Autodesk Fusion 360 part; units mm, degrees
(part 2 of 3)
sketch "Sketch2" plane through (0, 0, 6.35) normal (0, 0, 1) x (-1, 0, 0)
  line L0 (0, -44.45) -> (0, 0)
  line L1 (0, 0) -> (-41.148, 0)
  line L2 (-41.148, 0) -> (-41.148, -44.45)
  line L3 (-41.148, -44.45) -> (0, -44.45)
  line L4 (0, 0) -> (0, -38.608) construction
  line L5 (0, -38.608) -> (-41.148, -38.608)
  line L6 (-41.148, -38.608) -> (-41.148, -44.45)
  line L7 (-41.148, -44.45) -> (0, -44.45)
  line L8 (0, -44.45) -> (0, -38.608)
  dimension "d5" = 38.608
  constraint coincident L0.end L1.start
  constraint perpendicular L1 L4
  constraint horizontal L5
  constraint vertical L6
  constraint horizontal L7
  constraint vertical L8
  constraint coincident L2.end L3.start
  measures "d5" distance of L0.end L4.end
extrude "Extrude2" add sketch "Sketch2" along normal blind 22.86 contours L0 L2 L3 L5 L6 L7 L8
sketch "Sketch3" plane through (0, 0, 29.21) normal (0, 0, 1) x (-1, 0, 0)
  line L0 (0, -44.45) -> (0, -38.608)
  line L1 (0, -38.608) -> (-41.148, -38.608)
  line L2 (-41.148, -38.608) -> (-41.148, -44.45)
  line L3 (-41.148, -44.45) -> (0, -44.45)
  line L4 (-41.148, -44.45) -> (0, -44.45)
  line L5 (0, -44.45) -> (0, 0)
  line L6 (0, 0) -> (-41.148, 0)
  line L7 (-41.148, 0) -> (-41.148, -44.45)
  constraint horizontal L4
  constraint vertical L5
  constraint horizontal L6
  constraint vertical L7
  constraint coincident L5.end L6.start
  constraint coincident L2.end L3.start
extrude "Extrude3" add sketch "Sketch3" along normal blind 6.35
sketch "Sketch4" plane through (0, 44.45, 0) normal (0, 1, 0) x (-1, 0, 0)
  line L0 (-41.148, 0) -> (0, 0)
  line L1 (0, 0) -> (0, 35.56)
  line L2 (0, 35.56) -> (-41.148, 35.56)
  line L3 (-41.148, 35.56) -> (-41.148, 0)
  line L4 (-41.148, 17.78) -> (-33.528, 17.78) construction
  line L5 (-33.528, 17.78) -> (-30.353, 17.78) construction
  line L6 (-30.353, 8.255) -> (-41.148, 8.255)
  line L7 (-41.148, 8.255) -> (-41.148, 27.305)
  line L8 (-41.148, 27.305) -> (-30.353, 27.305)
  line L9 (-30.353, 27.305) -> (-30.353, 8.255)
  line L10 (-20.574, 35.56) -> (-20.574, 0) construction
  line L11 (-10.795, 27.305) -> (-10.795, 8.255)
  line L12 (0, 27.305) -> (-10.795, 27.305)
  line L13 (0, 8.255) -> (0, 27.305)
  line L14 (-10.795, 8.255) -> (0, 8.255)
  dimension "d10" = 7.62
  dimension "d11" = 3.175
  dimension "d13" = 19.05
  constraint midpoint L3 L4.start
  constraint perpendicular L3 L4
  constraint horizontal L5
  constraint horizontal L6
  constraint vertical L7
  constraint horizontal L8
  constraint vertical L9
  constraint midpoint L5.end L9
  constraint midpoint L2 L10.start
  constraint midpoint L0 L10.end
  constraint symmetric L6.start L10 L11.end
  constraint symmetric L6.end L10 L13.start
  constraint symmetric L7.end L10 L12.start
  constraint symmetric L8.end L10 L11.start
  measures "d10" distance of L4.start L4.end
  measures "d11" distance of L4.end L5.end
  measures "d13" distance of L6.start L8.end
extrude "Extrude4" cut sketch "Sketch4" against normal up to surface (5.842 mm away) contours L3 L6 L7 L8 L9 | L1 L11 L12 L13 L14
fillet "Fillet2" radius 2.54 6 edges at (20.574, 0, 29.21) (41.148, 0, 32.385) (0, 0, 32.385) (20.574, 0, 6.35) (41.148, 0, 3.175) (0, 0, 3.175)
fillet "Fillet4" radius 2.54 4 edges at (30.353, 41.529, 8.255) (10.795, 41.529, 8.255) (10.795, 41.529, 27.305) (30.353, 41.529, 27.305)
fillet "Fillet4" radius 2.54 2 edges at (20.574, 38.608, 6.35) (20.574, 38.608, 29.21)
fillet "Fillet5" radius 1.778 4 edges at (41.148, 41.4887, 8.255) (41.148, 41.4887, 27.305) (0, 41.4887, 8.255) (0, 41.4887, 27.305)
sketch "Sketch5" plane through (30.353, 0, 0) normal (1, 0, 0) x (0, 1, 0)
  line L0 (44.45, 24.765) -> (38.608, 24.765)
  line L1 (38.608, 24.765) -> (38.608, 10.795)
  line L2 (38.608, 10.795) -> (44.45, 10.795)
  line L3 (44.45, 10.795) -> (44.45, 24.765)
  line L4 (38.608, 17.78) -> (44.45, 17.78) construction
  circle A0 centre (41.151, 17.78) radius 1.4
  line L5 (38.608, 17.78) -> (39.751, 17.78) construction
  dimension "d28" = 2.8
  dimension "d29" = 1.143
  constraint midpoint L1 L4.start
  constraint midpoint L3 L4.end
  constraint coincident L4 A0.centre
  constraint coincident A0 L5.end
  constraint coincident L4 L5.end
  measures "d28" diameter of A0
  measures "d29" distance of L4.start L5.end
extrude "Extrude5" cut sketch "Sketch5" against normal up to surface (19.558 mm away) contours A0

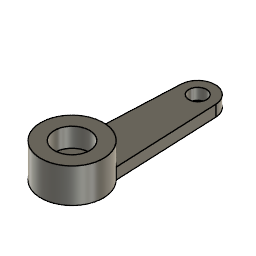
design "MicroServo horn"
Autodesk Fusion 360 part; units mm, degrees
sketch "Sketch1" plane through (0, 0, 0) normal (0, 0, 1) x (1, 0, 0)
  circle A0 centre (0, 0) radius 3.5243
  line L0 (-2.4892, 2.4948) -> (-1.9685, 14.2773)
  line L1 (2.4892, 2.4948) -> (1.9685, 14.2773)
  arc A1 (1.9685, 14.2773) -> (-1.9685, 14.2773) centre (0, 14.1903) ccw
  line L2 (-12.7, 16.1608) -> (12.7, 16.1608)
  line L3 (-12.7, -3.5242) -> (12.7, -3.5243)
  circle A2 centre (0, 14.1903) radius 1
  dimension "d1" = 7.0485
  dimension "d2" = 4.9784
  dimension "d5" = 19.685
  dimension "d7" = 3.937
  dimension "d8" = 2
  dimension "d9" = 25.4
  dimension "d10" = 12.7
  constraint coincident A0.centre origin
  constraint coincident A0 L0.start
  constraint coincident A0 L1.start
  constraint tangent L0 A1
  constraint horizontal L2
  constraint tangent A1 L2
  constraint vertical A0.centre A1.centre
  constraint horizontal L0.end L1.end
  constraint tangent A0 L3
  constraint horizontal L3
  constraint horizontal L0.start L1.start
  constraint concentric A1 A2
  constraint vertical L2.start L3.start
  constraint vertical L2.end L3.end
  measures "d1" diameter of A0
  measures "d2" horizontal distance of L0.start L1.start
  measures "d5" distance of L2 L3
  measures "d7" distance of L0.end L1.end
  measures "d8" diameter of A2
  measures "d9" distance of L2.start L2.end
  measures "d10" horizontal distance of A1.centre L2.start
extrude "Extrude1" add sketch "Sketch1" along normal blind 1.27
extrude "Extrude2" add sketch "Sketch1" along normal blind 3.8735 contours A0
sketch "Sketch2" plane through (0, 0, 3.8735) normal (0, 0, 1) x (-1, 0, 0)
  circle A0 centre (0, 0) radius 3.5242
  circle A1 centre (0, 0) radius 1.9812
  dimension "d15" = 3.9624
  constraint coincident A0.centre A1.centre
  measures "d15" diameter of A1
extrude "Extrude3" cut sketch "Sketch2" against normal blind 2.159 contours A1

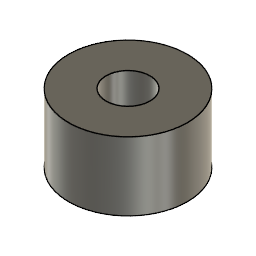
design "Shaft Collar"
Autodesk Fusion 360 part; units mm, degrees
sketch "Sketch1" plane through (0, 0, 0) normal (0, 0, 1) x (1, 0, 0)
  circle A0 centre (0, 0) radius 5.4991
  circle A1 centre (0, 0) radius 2.032
  dimension "d1" = 10.9982
  dimension "d2" = 4.064
  constraint coincident A0.centre A1.centre
  constraint concentric A0 A1
  measures "d1" diameter of A0
  measures "d2" diameter of A1
extrude "Extrude1" add sketch "Sketch1" along normal blind 6.35

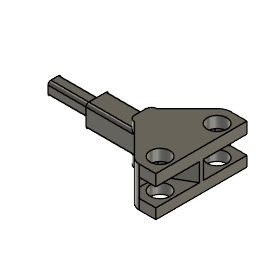
design "Wheel mount"
Autodesk Fusion 360 part; units mm, degrees
sketch "Sketch1" plane through (0, 0, 0) normal (0, 0, 1) x (1, 0, 0)
  line L0 (1.27, -2.54) -> (8.89, -2.54)
  line L1 (8.89, -2.54) -> (8.89, 2.54)
  line L2 (8.89, 2.54) -> (1.27, 2.54)
  line L3 (0, 1.27) -> (0, -1.27)
  line L4 (16.51, 10.16) -> (16.51, -10.16)
  line L5 (8.89, -10.16) -> (8.89, 10.16)
  arc A0 (1.27, 2.54) -> (0, 1.27) centre (1.27, 1.27) ccw
  arc A1 (0, -1.27) -> (1.27, -2.54) centre (1.27, -1.27) ccw
  circle A2 centre (10.795, 6.35) radius 2.2
  circle A3 centre (10.795, -6.35) radius 2.2
  line L6 (9.9421, 10.16) -> (16.51, 10.16)
  line L7 (9.9421, -10.16) -> (16.51, -10.16)
  line L8 (1.27, -2.54) -> (8.1461, -9.4161)
  line L9 (1.27, 2.54) -> (8.1461, 9.4161)
  arc A4 (9.9421, 10.16) -> (8.1461, 9.4161) centre (9.9421, 7.62) ccw
  arc A5 (8.1461, -9.4161) -> (9.9421, -10.16) centre (9.9421, -7.62) ccw
  line L10 (13.6525, 10.16) -> (13.6525, -10.16)
  dimension "d1" = 1.27
  dimension "d2" = 1.27
  dimension "d5" = 4.4
  dimension "d6" = 4.4
  dimension "d8" = 20.32
  dimension "d9" = 7.62
  dimension "d10" = 1.905
  dimension "d13" = 2.54
  dimension "d14" = 20.32
  dimension "d15" = 2.54
  dimension "d16" = 2.54
  dimension "d17" = 45
  dimension "d18" = 12.7
  dimension "d19" = 6.35
  dimension "d31" = 2.8575
  constraint horizontal L0
  constraint vertical L1
  constraint horizontal L2
  constraint vertical L3
  constraint vertical L4
  constraint vertical L5
  constraint midpoint L1 L5
  constraint tangent L2 A0
  constraint tangent L3 A0
  constraint tangent L0 A1
  constraint tangent L3 A1
  constraint midpoint origin L3
  constraint perpendicular L4 L6
  constraint coincident L5.end L9
  constraint coincident L5.end L6
  constraint tangent L9 A4
  constraint tangent L6 A4
  constraint coincident L5.start L8
  constraint coincident L5.start L7
  constraint tangent L8 A5
  constraint tangent L7 A5
  constraint vertical A2.centre A3.centre
  constraint coincident L6 L10.start
  constraint coincident L7 L10.end
  constraint perpendicular L7 L10
  measures "d1" radius of A0
  measures "d2" radius of A1
  measures "d5" diameter of A2
  measures "d6" diameter of A3
  measures "d8" distance of L4.start L4.end
  measures "d9" distance of L4 L5
  measures "d10" distance of L5 A3.centre
  measures "d13" distance of L3.start L3.end
  measures "d14" distance of L5.end L5.start
  measures "d15" radius of A4
  measures "d16" radius of A5
  measures "d17" angle of L0 L8
  measures "d18" vertical distance of A2.centre A3.centre
  measures "d19" vertical distance of origin A2.centre
  measures "d31" distance of A3.centre L10
extrude "Extrude1" add sketch "Sketch1" along normal blind 6.35 contours L0 L1 L2 L3 L5 A0 A1 | L0 L5 A3 L8 A5 | L1 L5 A2 A3 L6 L7 A4 A5 L10 | L2 L5 A2 L9 A4
sketch "Sketch3" plane through (13.6525, 0, 0) normal (1, 0, 0) x (0, 1, 0)
  line L0 (-10.16, 0) -> (10.16, 0)
  line L1 (10.16, 0) -> (10.16, 6.35)
  line L2 (10.16, 6.35) -> (-10.16, 6.35)
  line L3 (-10.16, 6.35) -> (-10.16, 0)
  line L4 (3.81, 5.08) -> (8.89, 5.08)
  line L5 (8.89, 5.08) -> (8.89, 1.27)
  line L6 (8.89, 1.27) -> (3.81, 1.27)
  line L7 (3.81, 1.27) -> (3.81, 5.08)
  line L8 (-10.16, 0) -> (10.16, 0)
  line L9 (10.16, 0) -> (10.16, 6.35)
  line L10 (10.16, 6.35) -> (-10.16, 6.35)
  line L11 (-10.16, 6.35) -> (-10.16, 0)
  line L12 (-8.89, 5.08) -> (-3.81, 5.08)
  line L13 (-3.81, 5.08) -> (-3.81, 1.27)
  line L14 (-3.81, 1.27) -> (-8.89, 1.27)
  line L15 (-8.89, 1.27) -> (-8.89, 5.08)
  dimension "d25" = 3.81
  dimension "d26" = 5.08
  dimension "d27" = 1.27
  dimension "d28" = 1.27
  dimension "d32" = 5.08
  dimension "d33" = 1.27
  dimension "d34" = 1.27
  dimension "d35" = 3.81
  constraint horizontal L4
  constraint vertical L5
  constraint horizontal L6
  constraint vertical L7
  constraint horizontal L12
  constraint vertical L13
  constraint horizontal L14
  constraint vertical L15
  measures "d25" distance of L4.end L5.end
  measures "d26" distance of L4.start L4.end
  measures "d27" distance of L1 L5
  measures "d28" distance of L0 L6
  measures "d32" distance of L12.start L12.end
  measures "d33" distance of L3 L15
  measures "d34" distance of L0 L14
  measures "d35" distance of L12.end L13.end
extrude "Extrude3" cut sketch "Sketch3" against normal blind 5.842 contours L4 L5 L6 L7 | L12 L13 L14 L15
sketch "Sketch2" plane through (0, 0, 0) normal (-1, 0, 0) x (0, -1, 0)
  line L0 (-1.27, 0) -> (1.27, 0)
  line L1 (1.27, 0) -> (1.27, 6.35)
  line L2 (1.27, 6.35) -> (-1.27, 6.35)
  line L3 (-1.27, 6.35) -> (-1.27, 0)
  line L4 (2.54, 5.715) -> (-2.54, 5.715)
  line L5 (-2.54, 5.715) -> (-2.54, 0.635)
  line L6 (-2.54, 0.635) -> (2.54, 0.635)
  line L7 (2.54, 0.635) -> (2.54, 5.715)
  line L8 (2.54, 5.715) -> (-2.54, 0.635) construction
  line L9 (-2.54, 5.715) -> (2.54, 0.635) construction
  point P0 (0, 3.175)
  dimension "d20" = 5.08
  dimension "d21" = 5.08
  dimension "d22" = 3.175
  constraint horizontal L4
  constraint perpendicular L4 L5
  constraint parallel L4 L6
  constraint parallel L5 L7
  constraint coincident L8 P0
  constraint coincident L9 P0
  constraint vertical origin P0
  measures "d20" distance of L4.end L5.end
  measures "d21" distance of L5.end L6.end
  measures "d22" vertical distance of origin P0
extrude "Extrude2" add sketch "Sketch2" along normal blind 19.05 contours L3 L4 L5 L6 | L1 L3 L4 L6 | L1 L4 L6 L7
draft "Draft1" angle 30 neutral plane through (7.8105, 0, 0) pull (1, 0, 0) 1 faces at (11.7052, -8.89, 2.54)
draft "Draft2" angle 30 neutral plane through (7.8105, 0, 0) pull (1, 0, 0) 1 faces at (11.7052, -3.81, 3.81)
draft "Draft3" angle 30 neutral plane through (7.8105, 0, 0) pull (1, 0, 0) 1 faces at (11.7052, 3.81, 2.54)
draft "Draft4" angle 30 neutral plane through (7.8105, 0, 0) pull (1, 0, 0) 1 faces at (9.7578, 8.89, 3.81)
extrude "Extrude4" add 1 faces at (3.4502, 0.4745, 6.35) along direction (0, 0, 1) blind 1.27
extrude "Extrude5" add 1 faces at (3.4502, 0.4745, 0) along direction (0, 0, -1) blind 1.27
extrude "Extrude6" cut 2 faces at (10.5895, -2.8174, 1.27) (10.5895, 2.8174, 1.27) along direction (0, 0, -1) blind 0.254
sketch "Sketch5" plane through (-19.05, 0, 0) normal (-1, 0, 0) x (0, -1, 0)
  line L0 (2.54, 0.635) -> (2.54, 5.715)
  line L1 (2.54, 5.715) -> (-2.54, 5.715)
  line L2 (-2.54, 5.715) -> (-2.54, 0.635)
  line L3 (-2.54, 0.635) -> (2.54, 0.635)
  line L4 (1.4875, 4.6625) -> (-1.4875, 4.6625)
  line L5 (-1.4875, 4.6625) -> (-1.4875, 1.6875)
  line L6 (-1.4875, 1.6875) -> (1.4875, 1.6875)
  line L7 (1.4875, 1.6875) -> (1.4875, 4.6625)
  line L8 (1.4875, 4.6625) -> (-1.4875, 1.6875) construction
  line L9 (-1.4875, 4.6625) -> (1.4875, 1.6875) construction
  point P0 (0, 3.175)
  point P1 (-10.16, -1.27)
  dimension "d50" = 2.975
  dimension "d51" = 2.975
  dimension "d52" = 4.445
  constraint horizontal L4
  constraint perpendicular L4 L5
  constraint parallel L4 L6
  constraint parallel L5 L7
  constraint coincident L8 P0
  constraint coincident L9 P0
  constraint vertical origin P0
  measures "d50" distance of L5 L7
  measures "d51" distance of L4 L6
  measures "d52" vertical distance of P0 P1
extrude "Extrude7" cut sketch "Sketch5" against normal blind 9.525
extrude "Extrude8" add 2 faces at (0, 1.6933, 2.54) (0, -1.6598, 3.81) along direction (1, 0, 0) blind 2.286
fillet "Fillet1" radius 0.635 8 edges at (-4.1275, 2.54, 5.715) (-4.1275, 2.54, 0.635) (-14.2875, 1.4875, 4.6625) (-14.2875, 1.4875, 1.6875) (-14.2875, -1.4875, 4.6625) (-14.2875, -1.4875, 1.6875) (-4.1275, -2.54, 5.715) (-4.1275, -2.54, 0.635)
equation "d10 = 0.125 in - 0.05 in"
equation "d31 = 0.165 * 0.5 in + 0.03 in"
equation "d50 = 0.125 in - 0.2 mm"
equation "d51 = 0.125 in - 0.2 mm"

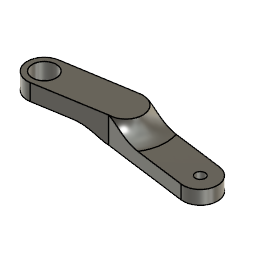
design "Right Control Arm"
Autodesk Fusion 360 part; units mm, degrees
sketch "Sketch1" plane through (0, 0, 0) normal (0, 0, 1) x (1, 0, 0)
  circle A0 centre (0, 0) radius 2.2
  circle A1 centre (28.829, 0) radius 0.9
  circle A2 centre (0, 0) radius 3.175
  circle A3 centre (28.829, 0) radius 3.175
  circle A4 centre (12.954, 2.0955) radius 3.175
  line L0 (28.407994, -3.146963) -> (12.954, -1.0795)
  line L1 (0.517136, -3.132602) -> (12.954, -1.0795)
  line L2 (29.244496, 3.147696) -> (13.369496, 5.243196)
  line L3 (-0.507012, 3.134256) -> (12.446988, 5.229756)
  dimension "d1" = 1.8
  dimension "d2" = 4.4
  dimension "d3" = 28.829
  dimension "d4" = 6.35
  dimension "d5" = 6.35
  dimension "d12" = 6.35
  dimension "d22" = 15.875
  dimension "d23" = 2.0955
  constraint coincident A0.centre A2.centre
  constraint concentric A1 A3
  constraint horizontal A0.centre A1.centre
  constraint coincident A4 L0.end
  constraint tangent A4 L2
  constraint tangent A4 L3
  constraint tangent A3 L2
  constraint tangent A3 L0
  constraint tangent A2 L1
  constraint tangent A2 L3
  constraint vertical A4.centre L0.end
  measures "d1" diameter of A1
  measures "d2" diameter of A0
  measures "d3" distance of A0.centre A1.centre
  measures "d4" diameter of A3
  measures "d5" diameter of A2
  measures "d12" diameter of A4
  measures "d22" horizontal distance of A1.centre A4.centre
  measures "d23" vertical distance of A1.centre A4.centre
extrude "Extrude1" add sketch "Sketch1" along normal blind 2.54 contours A4 | A3 A4 L0 L2 | A3 picked at (13.359471, 1.020697) picked at (22.492534, 0.825939) picked at (28.326881, -2.357846)
extrude "Extrude4" add sketch "Sketch1" along normal blind 5.588 contours A4 picked at (13.359471, 1.020697)
extrude "Extrude3" add sketch "Sketch1" along normal blind 5.588 and the other way blind -1.778 contours A2 | A2 A4 L1 L3 | A4 picked at (-0.65517, 2.767544) picked at (7.597762, 1.223874) picked at (13.359471, 1.020697)
extrude "Extrude5" cut 1 faces at (9.192139, 1.492716, 5.588) along direction (0, 0, -1) blind 0.762
fillet "Fillet1" radius 5.08 1 edges at (16.122167, 1.887304, 2.54)
fillet "Fillet2" radius 5.08 1 edges at (9.789202, 1.841177, 1.778)
sketch "Sketch2" plane through (0, 0, 0) normal (0, 0, -1) x (1, 0, 0)
  circle A0 centre (28.2448, 0) radius 1.5
  line L0 (16.8148, -3.175) -> (28.2448, -3.175)
  arc A1 (28.2448, -3.175) -> (28.2448, 3.175) centre (28.2448, 0) ccw
  line L1 (28.2448, 3.175) -> (16.8148, 3.175)
  circle A2 centre (0, 0) radius 2.0955
  circle A3 centre (0, 0) radius 3.175
  arc A4 (16.8148, 3.175) -> (16.8148, -3.175) centre (16.8148, 0) ccw
  dimension "d8" = 4.191
  dimension "d9" = 6.35
  measures "d8" diameter of A2
  measures "d9" diameter of A3
extrude "Extrude2" [suppressed]
equation "d3 = 1.235 in - 0.1 in"
equation "d23 = ( 0.165 / 2 ) * 1 in"

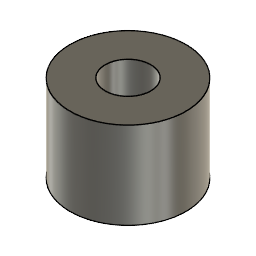
design "Front bushing"
Autodesk Fusion 360 part; units mm, degrees
sketch "Sketch1" plane through (0, 0, 0) normal (0, 0, 1) x (1, 0, 0)
  circle A0 centre (0, 0) radius 6.35
  circle A1 centre (0, 0) radius 2.4956
  dimension "d1" = 12.7
  dimension "d2" = 4.9911
  constraint coincident A0.centre A1.centre
  measures "d1" diameter of A0
  measures "d2" diameter of A1
extrude "Extrude1" add sketch "Sketch1" along normal blind 9.525

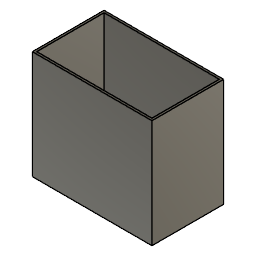
design "Recepticle"
Autodesk Fusion 360 part; units mm, degrees
sketch "Sketch1" plane through (0, 0, 0) normal (0, 0, 1) x (1, 0, 0)
  line L0 (0, 0) -> (127, 0)
  line L1 (127, 0) -> (127, 76.2)
  line L2 (127, 76.2) -> (0, 76.2)
  line L3 (0, 76.2) -> (0, 0)
  line L4 (124.6819, 73.8819) -> (2.3181, 73.8819)
  line L5 (2.3181, 73.8819) -> (2.3181, 2.3181)
  line L6 (2.3181, 2.3181) -> (124.6819, 2.3181)
  line L7 (124.6819, 2.3181) -> (124.6819, 73.8819)
  dimension "d1" = 127
  dimension "d2" = 76.2
  dimension "d3" = -2.3181
  constraint horizontal L0
  constraint vertical L1
  constraint horizontal L2
  constraint vertical L3
  constraint coincident L0.start L3.end
  measures "d1" distance of L0.start L0.end
  measures "d2" distance of L0.start L2.end
extrude "Extrude1" add sketch "Sketch1" along normal blind 115
extrude "Extrude2" add sketch "Sketch1" along normal blind 2.54 contours L4 L5 L6 L7

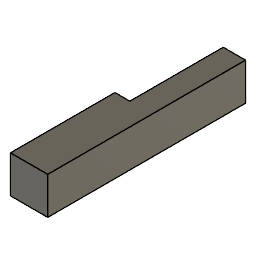
design "Right Fake Cross Beam"
Autodesk Fusion 360 part; units mm, degrees
sketch "Sketch1" plane through (0, 0, 0) normal (1, 0, 0) x (0, 1, 0)
  circle A0 centre (0, 0) radius 2.1971
  circle A1 centre (25.4, 0) radius 2.1971
  line L0 (10.16, 2.54) -> (15.24, 2.54)
  line L1 (15.24, 2.54) -> (15.24, -2.54)
  line L2 (15.24, -2.54) -> (10.16, -2.54)
  line L3 (10.16, -2.54) -> (10.16, 2.54)
  line L4 (-6.35, 4.7625) -> (31.75, 4.7625)
  line L5 (31.75, 4.7625) -> (31.75, -4.7625)
  line L6 (31.75, -4.7625) -> (-6.35, -4.7625)
  line L7 (-6.35, -4.7625) -> (-6.35, 4.7625)
  dimension "d1" = 25.4
  dimension "d2" = 4.3942
  dimension "d3" = 4.3942
  dimension "d4" = 5.08
  dimension "d5" = 5.08
  dimension "d6" = 2.54
  dimension "d7" = 10.16
  dimension "d8" = 9.525
  dimension "d9" = 38.1
  dimension "d10" = 4.7625
  dimension "d11" = 6.35
  constraint horizontal A0.centre A1.centre
  constraint horizontal L0
  constraint vertical L1
  constraint horizontal L2
  constraint vertical L3
  constraint coincident A0.centre origin
  constraint horizontal L4
  constraint vertical L5
  constraint horizontal L6
  constraint vertical L7
  measures "d1" distance of A0.centre A1.centre
  measures "d2" diameter of A0
  measures "d3" diameter of A1
  measures "d4" distance of L0.start L0.end
  measures "d5" distance of L0.start L2.end
  measures "d6" distance of A0.centre L0
  measures "d7" horizontal distance of A0.centre L2.end
  measures "d8" distance of L4.start L6.end
  measures "d9" distance of L4.start L4.end
  measures "d10" distance of A0.centre L4
  measures "d11" distance of A0.centre L7
extrude "Extrude1" add sketch "Sketch1" along normal blind 2.54 contours A0 | A1 | L0 L1 L2 L3 | L4 L5 L6 L7 makes body 1
sketch "Sketch2" plane through (2.54, 0, 0) normal (1, 0, 0) x (0, 1, 0)
  line L0 (-6.35, -4.7625) -> (31.75, -4.7625)
  line L1 (31.75, -4.7625) -> (31.75, 4.7625)
  line L2 (31.75, 4.7625) -> (-6.35, 4.7625)
  line L3 (-6.35, 4.7625) -> (-6.35, -4.7625)
  line L4 (31.75, 4.7625) -> (-6.35, 4.7625)
  line L5 (-6.35, 4.7625) -> (-6.35, -4.7625)
  line L6 (-6.35, -4.7625) -> (31.75, -4.7625)
  line L7 (31.75, -4.7625) -> (31.75, 4.7625)
  circle A0 centre (0, 0) radius 2.1971
  circle A1 centre (25.4, 0) radius 2.1971
  dimension "d14" = 4.3942
  dimension "d15" = 4.3942
  constraint horizontal L4
  constraint vertical L5
  constraint horizontal L6
  constraint vertical L7
  constraint coincident L0.start L3.end
  constraint coincident L1.end L2.start
  measures "d14" diameter of A0
  measures "d15" diameter of A1
extrude "Extrude2" add sketch "Sketch2" along normal blind 3.81 contours L0 L1 L2 L3 L4 L5 L6 L7 | A0 | A1 bodies 1
sketch "Sketch3" plane through (0, -6.35, 0) normal (0, -1, 0) x (1, 0, 0)
  line L0 (0, 4.7625) -> (0, -4.7625)
  line L1 (0, -4.7625) -> (6.35, -4.7625)
  line L2 (6.35, -4.7625) -> (6.35, 4.7625)
  line L3 (6.35, 4.7625) -> (0, 4.7625)
  line L4 (0, 4.7625) -> (6.35, 4.7625)
  line L5 (6.35, 4.7625) -> (6.35, -4.7625)
  line L6 (6.35, -4.7625) -> (0, -4.7625)
  line L7 (0, -4.7625) -> (0, 4.7625)
  constraint horizontal L4
  constraint vertical L5
  constraint horizontal L6
  constraint vertical L7
  constraint coincident L1.end L2.start
  constraint coincident L0.start L3.end
extrude "Extrude3" add sketch "Sketch3" along normal blind 127 bodies 1
sketch "Sketch4" plane through (6.35, 0, 0) normal (1, 0, 0) x (0, 1, 0)
  line L0 (31.75, -4.7625) -> (31.75, 4.7625)
  line L1 (31.75, 4.7625) -> (-133.35, 4.7625)
  line L2 (-133.35, 4.7625) -> (-133.35, -4.7625)
  line L3 (-133.35, -4.7625) -> (31.75, -4.7625)
  circle A0 centre (-22.225, -1.5875) radius 1.6
  circle A1 centre (-47.625, -1.5875) radius 1.6
  dimension "d20" = 3.2
  dimension "d21" = 3.2
  dimension "d24" = 6.35
  dimension "d25" = 22.225
  dimension "d48" = 25.4
  constraint horizontal A0.centre A1.centre
  measures "d20" diameter of A0
  measures "d21" diameter of A1
  measures "d24" distance of L1 A0.centre
  measures "d25" horizontal distance of origin A0.centre
  measures "d48" distance of A0.centre A1.centre
sketch "Sketch5" plane through (0, -133.35, 0) normal (0, -1, 0) x (1, 0, 0)
  line L0 (0, -4.7625) -> (6.35, -4.7625)
  line L1 (6.35, -4.7625) -> (6.35, 4.7625)
  line L2 (6.35, 4.7625) -> (0, 4.7625)
  line L3 (0, 4.7625) -> (0, -4.7625)
  line L4 (0, -4.7625) -> (6.35, -4.7625)
  line L5 (6.35, -4.7625) -> (6.35, 1.5875)
  line L6 (6.35, 1.5875) -> (0, 1.5875)
  line L7 (0, 1.5875) -> (0, -4.7625)
  dimension "d29" = 6.35
  constraint horizontal L4
  constraint vertical L5
  constraint horizontal L6
  constraint vertical L7
  constraint coincident L1 L5.end
  constraint coincident L0.start L3.end
  measures "d29" distance of L0.end L5.end
extrude "Extrude5" cut sketch "Sketch5" against normal blind 67.945 contours L1 L2 L3 L6 bodies 1
sketch "Sketch6" plane through (0, 0, 0) normal (-1, 0, 0) x (0, -1, 0)
  line L0 (65.405, 1.5875) -> (65.405, 4.7625)
  line L1 (65.405, 4.7625) -> (-31.75, 4.7625)
  line L2 (-31.75, 4.7625) -> (-31.75, -4.7625)
  line L3 (-31.75, -4.7625) -> (133.35, -4.7625)
  line L4 (133.35, -4.7625) -> (133.35, 1.5875)
  line L5 (133.35, 1.5875) -> (65.405, 1.5875)
  circle A0 centre (117.475, -1.5875) radius 2.1
  dimension "d32" = 4.2
  dimension "d33" = 15.875
  dimension "d34" = 3.175
  measures "d32" diameter of A0
  measures "d33" distance of L4 A0.centre
  measures "d34" distance of L3 A0.centre
extrude "Extrude6" cut sketch "Sketch6" against normal blind 6.35 contours A0 bodies 1
sketch "Sketch7" plane through (6.35, 0, 0) normal (1, 0, 0) x (0, 1, 0)
  circle A0 centre (-117.475, -1.5875) radius 2.1
  line L0 (-65.405, 4.7625) -> (-65.405, 1.5875)
  line L1 (-65.405, 1.5875) -> (-133.35, 1.5875)
  line L2 (-133.35, 1.5875) -> (-133.35, -4.7625)
  line L3 (-133.35, -4.7625) -> (31.75, -4.7625)
  line L4 (31.75, -4.7625) -> (31.75, 4.7625)
  line L5 (31.75, 4.7625) -> (-65.405, 4.7625)
  circle A1 centre (-117.475, -11.4427) radius 2.1
  circle A2 centre (-117.475, -11.4427) radius 3.175
  circle A3 centre (-106.045, -11.4427) radius 2.1
  circle A4 centre (-106.045, -11.4427) radius 3.175
  line L6 (-117.475, -8.2677) -> (-106.045, -8.2677)
  line L7 (-117.475, -14.6177) -> (-106.045, -14.6177)
  line L8 (-65.405, 4.7625) -> (-65.405, -4.7625)
  line L9 (-106.045, -14.6177) -> (-70.9402, -14.6177)
  line L10 (-70.9402, -14.6177) -> (-65.405, -6.5046)
  line L11 (-106.045, -8.2677) -> (-74.295, -8.2677)
  line L12 (-74.295, -8.2677) -> (-65.405, 4.7625)
  line L13 (-65.405, -6.5046) -> (-65.405, -4.7625)
  line L14 (-65.405, -6.5046) -> (-64.2164, -4.7625)
  line L15 (-120.65, -8.2677) -> (-102.87, -8.2677)
  line L16 (-102.87, -8.2677) -> (-102.87, -14.6177)
  line L17 (-102.87, -14.6177) -> (-120.65, -14.6177)
  line L18 (-120.65, -14.6177) -> (-120.65, -8.2677)
  dimension "d37" = 9.8552
  dimension "d38" = 6.35
  dimension "d43" = 4.2
  dimension "d44" = 6.35
  dimension "d45" = 11.43
  dimension "d49" = 31.75
  dimension "d50" = 6.35
  constraint equal A0 A1
  constraint vertical A0.centre A1.centre
  constraint concentric A1 A2
  constraint concentric A3 A4
  constraint horizontal A1.centre A3.centre
  constraint coincident A2 L6.start
  constraint coincident A4 L6.end
  constraint parallel L3 L6
  constraint coincident A2 L7.start
  constraint coincident A4 L7.end
  constraint coincident L3 L8.end
  constraint horizontal L7
  constraint tangent A2 L7
  constraint tangent A2 L6
  constraint vertical L8.end L0.start
  constraint tangent A4 L9
  constraint parallel L3 L9
  constraint coincident L8 L10.end
  constraint tangent A4 L11
  constraint parallel L3 L11
  constraint coincident L0.start L5.end
  constraint vertical L0.start L5.end
  constraint parallel L10 L12
  constraint coincident L3 L14.end
  constraint parallel L10 L14
  constraint horizontal L15
  constraint vertical L16
  constraint horizontal L17
  constraint vertical L18
  constraint coincident L9 L16.end
  constraint tangent A4 L16
  constraint tangent A2 L18
  constraint coincident L11 L15.end
  measures "d37" vertical distance of A0.centre A1.centre
  measures "d38" diameter of A2
  measures "d43" diameter of A3
  measures "d44" diameter of A4
  measures "d45" distance of A1.centre A3.centre
  measures "d49" horizontal distance of A3.centre L11.end
  measures "d50" distance of L10 L12
extrude "Extrude7" cut sketch "Sketch7" against normal blind 6.35 contours L0 L1 L8 L12 | L1 L3 L8 L12 | L1 L2 L3 L12 bodies 1
extrude "Extrude8" add sketch "Sketch7" against normal blind 3.81 separate body contours L0 L1 L8 L12 | L1 L3 L8 L12 | L3 L9 L10 L11 L12 L13 L16 | L3 L13 L14 | A4 L11 L15 L16 | A4 L9 L16 L17 | A4 | A2 A4 L6 L7 L15 L17 | A2 | A2 L15 L18 | A2 L17 L18 | A1 | A3 makes body 2
extrude "Extrude9" add sketch "Sketch7" against normal blind 6.35 contours A4 L11 L15 L16 | A4 L9 L16 L17 | A4 | A2 A4 L6 L7 L15 L17 | A2 | A2 L15 L18 | A2 L17 L18 | A1 | A3 bodies 2
sketch "Sketch8" plane through (0, 0, 4.7625) normal (0, 0, 1) x (-1, 0, 0)
  line L0 (0, 65.405) -> (-6.35, 65.405)
  line L1 (-6.35, 65.405) -> (-6.35, -31.75)
  line L2 (-6.35, -31.75) -> (0, -31.75)
  line L3 (0, -31.75) -> (0, 65.405)
  line L4 (0, -31.75) -> (-6.35, -31.75)
  line L5 (-6.35, -31.75) -> (-6.35, 65.405)
  line L6 (-6.35, 65.405) -> (0, 65.405)
  line L7 (0, 65.405) -> (0, -31.75)
  constraint horizontal L4
  constraint vertical L5
  constraint horizontal L6
  constraint vertical L7
  constraint coincident L0.end L1.start
  constraint coincident L2.end L3.start
extrude "Extrude10" add sketch "Sketch8" along normal blind 0.4318 bodies 1 2
sketch "Sketch9" plane through (0, 31.75, 0) normal (0, 1, 0) x (-1, 0, 0)
  line L0 (0, -4.7625) -> (0, 5.1943)
  line L1 (0, 5.1943) -> (-6.35, 5.1943)
  line L2 (-6.35, 5.1943) -> (-6.35, -4.7625)
  line L3 (-6.35, -4.7625) -> (0, -4.7625)
  line L4 (-6.35, -4.7625) -> (0, -4.7625)
  line L5 (0, -4.7625) -> (0, 5.1943)
  line L6 (0, 5.1943) -> (-6.35, 5.1943)
  line L7 (-6.35, 5.1943) -> (-6.35, -4.7625)
  constraint horizontal L4
  constraint vertical L5
  constraint horizontal L6
  constraint vertical L7
  constraint coincident L0.end L1.start
  constraint coincident L2.end L3.start
extrude "Extrude11" add sketch "Sketch9" along normal blind 12.7 bodies 1
sketch "Sketch10" plane through (0, 0, -4.7625) normal (0, 0, -1) x (1, 0, 0)
  line L0 (6.35, 64.2164) -> (2.54, 64.2164)
  line L1 (2.54, 64.2164) -> (2.54, 65.405)
  line L2 (2.54, 65.405) -> (0, 65.405)
  line L3 (0, 65.405) -> (0, -44.45)
  line L4 (0, -44.45) -> (6.35, -44.45)
  line L5 (6.35, -44.45) -> (6.35, 64.2164)
  line L6 (6.35, -44.45) -> (0, -44.45)
  line L7 (0, -44.45) -> (0, 6.35)
  line L8 (0, 6.35) -> (6.35, 6.35)
  line L9 (6.35, 6.35) -> (6.35, -44.45)
  dimension "d55" = 50.8
  constraint horizontal L6
  constraint vertical L7
  constraint horizontal L8
  constraint vertical L9
  constraint coincident L3 L7.end
  constraint coincident L4.end L5.start
  measures "d55" distance of L4.end L8.end
extrude "Extrude12" add sketch "Sketch10" along normal blind 6.35 contours L3 L4 L5 L6 L7 L8 L9 bodies 1
sketch "Sketch11" plane through (0, 0, 0) normal (-1, 0, 0) x (0, -1, 0)
  line L0 (65.405, -4.7625) -> (65.405, 5.1943)
  line L1 (65.405, 5.1943) -> (-44.45, 5.1943)
  line L2 (-44.45, 5.1943) -> (-44.45, -11.1125)
  line L3 (-44.45, -11.1125) -> (6.35, -11.1125)
  line L4 (6.35, -11.1125) -> (6.35, -4.7625)
  line L5 (6.35, -4.7625) -> (65.405, -4.7625)
  line L6 (-44.45, 5.1943) -> (-44.45, -4.9657)
  line L7 (0.4841, -4.9657) -> (6.35, 5.1943)
  line L8 (-44.45, -4.9657) -> (0.4841, -4.9657)
  dimension "d58" = 60
  dimension "d59" = 50.8
  dimension "d60" = 10.16
  constraint coincident L1.end L2.start
  constraint coincident L1 L7.end
  constraint horizontal L8
  constraint vertical L6
  measures "d58" angle of L1 L7
  measures "d59" distance of L1.end L7.end
  measures "d60" distance of L1.end L6.end
extrude "Extrude13" cut sketch "Sketch11" against normal blind 6.35 contours L1 L2 L6 L7 L8 bodies 1
fillet "Fillet1" radius 19.05 1 edges at (3.175, -6.35, -4.7625) on bodies 1
fillet "Fillet2" radius 6.35 1 edges at (3.175, -0.4841, -4.9657) on bodies 1
sketch "Sketch13" plane through (0, 44.45, 0) normal (0, 1, 0) x (-1, 0, 0)
  line L0 (0, -4.9657) -> (-6.35, -4.9657)
  line L1 (-6.35, -4.9657) -> (-6.35, -11.1125)
  line L2 (-6.35, -11.1125) -> (0, -11.1125)
  line L3 (0, -11.1125) -> (0, -4.9657)
  line L4 (-26.6046, 16.2746) -> (24.1954, 16.2746)
  line L5 (24.1954, 16.2746) -> (24.1954, -34.5254)
  line L6 (24.1954, -34.5254) -> (-26.6046, -34.5254)
  line L7 (-26.6046, -34.5254) -> (-26.6046, 16.2746)
  dimension "d73" = 50.8
  dimension "d74" = 50.8
  dimension "d75" = 35.8333
  dimension "d76" = 24.1954
  constraint horizontal L4
  constraint vertical L5
  constraint horizontal L6
  constraint vertical L7
  measures "d73" distance of L4.start L6.end
  measures "d74" distance of L5.end L6.end
  measures "d75" distance of L0.end L6.end
  measures "d76" distance of L3 L5
extrude "Extrude17" cut sketch "Sketch13" against normal blind 118.745 contours L0 L1 L2 L3 | L4 L5 L6 L7 bodies 1
extrude "Extrude18" cut 1 faces at (5.08, -74.295, -10.3844) along direction (0, -1, 0) blind 12.7 on bodies 1 bodies 1
extrude "Extrude14" [suppressed]
extrude "Extrude15" [suppressed]
sketch "Sketch12" plane through (6.35, 0, 0) normal (1, 0, 0) x (0, 1, 0)
  line L0 (44.45, -4.9657) -> (3.1821, -4.9657)
  arc A0 (-2.3172, -1.7907) -> (3.1821, -4.9657) centre (3.1821, 1.3843) ccw
  line L1 (-2.3172, -1.7907) -> (-6.35, 5.1943)
  line L2 (-6.35, 5.1943) -> (-65.405, 5.1943)
  line L3 (-65.405, 5.1943) -> (-65.405, 4.7625)
  line L4 (-65.405, 4.7625) -> (-74.295, -8.2677)
  line L5 (-74.295, -8.2677) -> (-120.65, -8.2677)
  line L6 (-120.65, -8.2677) -> (-120.65, -14.6177)
  line L7 (-120.65, -14.6177) -> (-70.9402, -14.6177)
  line L8 (-70.9402, -14.6177) -> (-64.2164, -4.7625)
  line L9 (-64.2164, -4.7625) -> (-20.549, -4.7625)
  arc A1 (-6.35, -11.1125) -> (-20.549, -4.7625) centre (-20.549, -23.8125) ccw
  line L10 (-6.35, -11.1125) -> (44.45, -11.1125)
  line L11 (44.45, -11.1125) -> (44.45, -4.9657)
  line L12 (-74.295, -8.2677) -> (-74.295, -14.6177)
  constraint coincident L4.end L5.start
  constraint coincident L7 L12.end
  constraint perpendicular L7 L12
extrude "Extrude16" [suppressed]
equation "d7 = 0.5 in - ( 0.2 / 2 ) * 1 in"
equation "d10 = ( 0.375 / 2 ) * 1 in"
equation "d11 = ( ( 1.5 - 1 ) / 2 ) * 1 in"
equation "d37 = 0.263 in + 0.125 in"

design "6 pack"
Autodesk Fusion 360 part; units mm, degrees
sketch "Sketch1" plane through (0, 0, 0) normal (0, 0, 1) x (1, 0, 0)
  line L0 (0, 0) -> (97.79, 0)
  line L1 (97.79, 0) -> (97.79, 58.674)
  line L2 (97.79, 58.674) -> (0, 58.674)
  line L3 (0, 58.674) -> (0, 0)
  dimension "d1" = 58.674
  dimension "d2" = 97.79
  constraint horizontal L0
  constraint vertical L1
  constraint horizontal L2
  constraint vertical L3
  constraint coincident L0.start L3.end
  measures "d1" distance of L0.start L2.end
  measures "d2" distance of L0.start L0.end
extrude "Extrude1" add sketch "Sketch1" along normal blind 16.002

design "Left Control Arm"
Autodesk Fusion 360 part; units mm, degrees
sketch "Sketch1" plane through (0, 0, 0) normal (0, 0, 1) x (1, 0, 0)
  circle A0 centre (0, 0) radius 2.2
  circle A1 centre (28.829, 0) radius 0.9
  circle A2 centre (0, 0) radius 3.175
  circle A3 centre (28.829, 0) radius 3.175
  line L0 (28.161, 3.1039) -> (14.4145, 0.1454)
  line L1 (14.4145, 0.1454) -> (0.668, 3.1039)
  line L2 (29.497, -3.1039) -> (14.4145, -6.35)
  line L3 (14.4145, -6.35) -> (-0.668, -3.1039)
  dimension "d1" = 1.8
  dimension "d2" = 4.4
  dimension "d3" = 28.829
  dimension "d4" = 6.35
  dimension "d5" = 6.35
  dimension "d14" = 6.35
  constraint coincident A0.centre A2.centre
  constraint concentric A1 A3
  constraint horizontal A0.centre A1.centre
  constraint coincident A3 L0.start
  constraint coincident A2 L1.end
  constraint coincident A3 L2.start
  constraint parallel L0 L2
  constraint coincident A2 L3.end
  constraint tangent A2 L3
  constraint tangent A2 L1
  constraint tangent A3 L0
  constraint tangent A3 L2
  constraint parallel L1 L3
  constraint vertical L0.end L2.end
  measures "d1" diameter of A1
  measures "d2" diameter of A0
  measures "d3" distance of A0.centre A1.centre
  measures "d4" diameter of A3
  measures "d5" diameter of A2
  measures "d14" vertical distance of A1.centre L2.end
extrude "Extrude1" add sketch "Sketch1" along normal blind 2.54
sketch "Sketch3" plane through (0, 0, 0) normal (0, 0, -1) x (1, 0, 0)
  circle A0 centre (0, 0) radius 2.2
  circle A1 centre (28.829, 0) radius 0.9
  line L0 (0.668, -3.1039) -> (14.4145, -0.1454)
  line L1 (14.4145, -0.1454) -> (28.161, -3.1039)
  arc A2 (28.161, -3.1039) -> (29.497, 3.1039) centre (28.829, 0) ccw
  line L2 (29.497, 3.1039) -> (14.4145, 6.35)
  line L3 (14.4145, 6.35) -> (-0.668, 3.1039)
  arc A3 (-0.668, 3.1039) -> (0.668, -3.1039) centre (0, 0) ccw
  line L4 (14.4145, 6.35) -> (14.4145, -0.1454)
  circle A4 centre (0, 0) radius 3.175
  line L5 (14.4145, 6.35) -> (-0.668, 3.1039)
  line L6 (14.4145, -0.1454) -> (0.668, -3.1039)
  circle A5 centre (14.4145, 3.1023) radius 3.2477
  constraint coincident L2.end L3.start
  constraint coincident L0.end L1.start
  constraint coincident A0.centre A3.centre
  constraint coincident L3.end A3.start
  constraint tangent A4 L5
  constraint coincident L0.start A3.end
  constraint midpoint L4 A5.centre
  constraint coincident L2.end A5
extrude "Extrude3" add sketch "Sketch3" along normal blind 1.27 and the other way blind 1.905 contours L3 L4 L5 A5 | L2 L4 A5
sketch "Sketch2" plane through (0, 0, 0) normal (0, 0, -1) x (1, 0, 0)
  circle A0 centre (28.829, 0) radius 0.9
  arc A1 (28.161, -3.1039) -> (29.497, 3.1039) centre (28.829, 0) ccw
  circle A2 centre (0, 0) radius 2.0955
  circle A3 centre (0, 0) radius 3.175
  line L0 (14.4145, -0.1454) -> (28.161, -3.1039)
  line L1 (29.497, 3.1039) -> (15.7506, 6.0625)
  circle A4 centre (0, 0) radius 2.2
  line L2 (0.668, -3.1039) -> (14.4145, -0.1454)
  line L3 (13.0784, 6.0625) -> (-0.668, 3.1039)
  arc A5 (-0.668, 3.1039) -> (0.668, -3.1039) centre (0, 0) ccw
  arc A6 (14.4145, -0.1454) -> (15.7506, 6.0625) centre (14.4145, 3.1023) ccw
  arc A7 (13.0784, 6.0625) -> (14.4145, -0.1454) centre (14.4145, 3.1023) ccw
  dimension "d8" = 4.191
  dimension "d9" = 6.35
  measures "d8" diameter of A2
  measures "d9" diameter of A3
extrude "Extrude2" cut sketch "Sketch2" against normal blind 5.588 contours A3 L2 L3 A7 | A3 A5
sketch "Sketch4" plane through (0, 0, -1.27) normal (0, 0, -1) x (1, 0, 0)
  arc A0 (13.0784, 6.0625) -> (15.7506, 6.0625) centre (14.4145, 3.1023) ccw
  line L0 (15.7506, 6.0625) -> (14.4145, 6.35)
  line L1 (14.4145, 6.35) -> (13.0784, 6.0625)
  circle A1 centre (0, 0) radius 2.0955
  circle A2 centre (0, 0) radius 3.175
  line L2 (13.7465, 6.2062) -> (-0.668, 3.1039)
  line L3 (0.9727, -3.0223) -> (14.4145, -0.1454)
  dimension "d19" = 4.191
  dimension "d20" = 6.35
  dimension "d21" = 13.4418
  constraint coincident A1.centre A2.centre
  constraint concentric A1 A2
  constraint midpoint L1 L2.start
  constraint coincident A2 L2.end
  constraint tangent A2 L2
  constraint coincident A2 L3.start
  constraint midpoint A0 L3.end
  measures "d19" diameter of A1
  measures "d20" diameter of A2
  measures "d21" horizontal distance of L3.start L3.end
extrude "Extrude4" add sketch "Sketch4" along normal blind 1.27
extrude "Extrude5" add 1 faces at (4.0227, -3.2621, -1.27) along direction (0, 0, 1) blind 2.286
fillet "Fillet1" radius 5.08 1 edges at (11.2395, -2.419, 1.016)
fillet "Fillet2" radius 5.08 1 edges at (17.5895, -2.419, 0)
equation "d3 = 1.235 in - 0.1 in"

design "Yellow Motor Wheel"
Autodesk Fusion 360 part; units mm, degrees
sketch "Sketch4" plane through (0, 0, 0) normal (0, 0, 1) x (1, 0, 0)
  circle A0 centre (0, 0) radius 31.75
  dimension "d14" = 63.5
  constraint coincident A0.centre origin
  measures "d14" diameter of A0
extrude "Extrude4" add sketch "Sketch4" along normal blind 26.924
sketch "Sketch5" plane through (0, 0, 26.924) normal (0, 0, 1) x (-1, 0, 0)
  circle A0 centre (0, 0) radius 31.75
  circle A1 centre (0, 0) radius 2.7
  circle A2 centre (0, 0) radius 3.81
  dimension "d17" = 5.4
  dimension "d18" = 7.62
  constraint concentric A0 A1
  constraint concentric A1 A2
  measures "d17" diameter of A1
  measures "d18" diameter of A2
extrude "Extrude5" add sketch "Sketch5" along normal blind 2.54 contours A2
extrude "Extrude6" cut 1 faces at (-0.0791, 0.5246, 26.924) along direction (0, 0, -1) blind 5.36
equation "d21 = -0.0079 m + 0.1 in"

design "New Final Cross beam"
Autodesk Fusion 360 part; units mm, degrees
ref_plane "WorkPlane1" through (190.5, 0, 0) normal (1, 0, 0) x (0, 1, 0)
ref_plane "WorkPlane2" through (0, 0, 0) normal (1, 0, 0) x (0, 1, 0)
sketch "Sketch2" plane through (0, 0, 0) normal (1, 0, 0) x (0, 1, 0)
  line L0 (0, 0) -> (12.7, 0)
  line L1 (12.7, 0) -> (12.7, 12.7)
  line L2 (12.7, 12.7) -> (0, 12.7)
  line L3 (0, 12.7) -> (0, 0)
  dimension "d7" = 12.7
  dimension "d8" = 12.7
  constraint horizontal L0
  constraint vertical L1
  constraint horizontal L2
  constraint vertical L3
  constraint coincident L0.start L3.end
  measures "d7" distance of L0.start L0.end
  measures "d8" distance of L0.start L2.end
sketch "Sketch3" plane through (190.5, 0, 0) normal (1, 0, 0) x (0, 1, 0)
  line L0 (3.9116, 0) -> (15.3416, 0)
  line L1 (15.3416, 0) -> (15.3416, 12.7)
  line L2 (15.3416, 12.7) -> (3.9116, 12.7)
  line L3 (3.9116, 12.7) -> (3.9116, 0)
  dimension "d9" = 11.43
  dimension "d10" = 12.7
  dimension "d11" = 3.9116
  constraint horizontal L0
  constraint vertical L1
  constraint horizontal L2
  constraint vertical L3
  constraint horizontal origin L0.start
  measures "d9" distance of L0.start L0.end
  measures "d10" distance of L0.start L2.end
  measures "d11" distance of origin L3
loft "Loft1" add profiles "Sketch2", "Sketch3" section 1 section 2 makes body 1
sketch "Sketch4" plane through (0, 0, 0) normal (0, 0, -1) x (1, 0, 0)
  line L0 (0, 0) -> (0, -12.7)
  line L1 (0, -12.7) -> (190.5, -15.3416)
  line L2 (190.5, -15.3416) -> (190.5, -3.9116)
  line L3 (190.5, -3.9116) -> (0, 0)
  line L4 (190.5, -15.3416) -> (190.5, -3.9116)
  line L5 (156.845, -3.2206) -> (190.5, -3.9116)
  line L6 (156.845, -3.2206) -> (156.845, -14.8749)
  line L7 (190.5, -15.3416) -> (156.845, -14.8749)
  dimension "d12" = 33.655
  constraint coincident L1.end L2.start
  constraint coincident L2.end L3.start
  constraint coincident L3 L5.start
  constraint coincident L1 L6.end
  constraint parallel L4 L6
  measures "d12" horizontal distance of L1.end L6.end
extrude "Extrude2" add sketch "Sketch4" along normal blind 16.891 contours L1 L2 L3 L4 L5 L6 L7 bodies 1
sketch "Sketch5" plane through (0, 0, -16.891) normal (0, 0, -1) x (1, 0, 0)
  line L0 (156.845, -3.2206) -> (156.845, -14.8749)
  line L1 (156.845, -14.8749) -> (190.5, -15.3416)
  line L2 (190.5, -15.3416) -> (190.5, -3.9116)
  line L3 (190.5, -3.9116) -> (156.845, -3.2206)
  line L4 (190.5, -10.1919) -> (185.4208, -15.2712)
  dimension "d15" = 45
  dimension "d16" = 7.1831
  constraint coincident L2 L4.start
  constraint coincident L1 L4.end
  measures "d15" angle of L2 L4
  measures "d16" distance of L4.start L4.end
extrude "Extrude3" cut sketch "Sketch5" against normal blind 40.64 contours L1 L2 L4 bodies 1
sketch "Sketch6" plane through (-0.1761, 12.6976, 0) normal (-0.013865, 0.999904, 0) x (-0.999904, -0.013865, 0)
  line L0 (-185.6147, 12.7) -> (-185.6147, -16.891)
  line L1 (-185.6147, -16.891) -> (-157.0362, -16.891)
  line L2 (-157.0362, -16.891) -> (-157.0362, 0)
  line L3 (-157.0362, 0) -> (-0.1761, 0)
  line L4 (-0.1761, 0) -> (-0.1761, 12.7)
  line L5 (-0.1761, 12.7) -> (-185.6147, 12.7)
  line L6 (-190.623, 12.7) -> (-108.623, 12.7)
  line L7 (-108.623, 12.7) -> (-108.623, 0)
  line L8 (-108.623, 0) -> (-190.623, 0)
  line L9 (-190.623, 0) -> (-190.623, 12.7)
  point P0 (-190.623, 12.7)
  dimension "d19" = 82
  constraint horizontal L6
  constraint vertical L7
  constraint horizontal L8
  constraint vertical L9
  constraint coincident L3 L7.end
  constraint coincident L5 P0
  constraint coincident P0 L6.start
  measures "d19" distance of L7.end L8.end
extrude "Extrude4" add sketch "Sketch6" along normal blind 29.5808 contours L0 L3 L5 L6 L7 L8 | L0 L6 L8 L9 bodies 1
sketch "Sketch7" plane through (0, 0, 12.7) normal (0, 0, 1) x (-1, 0, 0)
  line L0 (-190.5, -10.1919) -> (-185.4208, -15.2712)
  line L1 (-190.4286, -15.3406) -> (-190.0185, -44.9186)
  line L2 (-190.0185, -44.9186) -> (-108.0263, -43.7816)
  line L3 (-108.0263, -43.7816) -> (-108.4365, -14.2037)
  line L4 (-108.4365, -14.2037) -> (0, -12.7)
  line L5 (0, -12.7) -> (0, 0)
  line L6 (0, 0) -> (-190.5, -3.9116)
  line L7 (-190.5, -3.9116) -> (-190.5, -10.1919)
  line L8 (-188.431, -40.6066) -> (-111.2013, -40.6066)
  line L9 (-111.2013, -40.6066) -> (-111.2013, -18.6066)
  line L10 (-111.2013, -18.6066) -> (-188.431, -18.6066)
  line L11 (-188.431, -18.6066) -> (-188.431, -40.6066)
  line L12 (-185.4208, -15.2712) -> (-190.4286, -15.3406)
  dimension "d23" = 1.5875
  dimension "d24" = 3.175
  dimension "d25" = 3.175
  dimension "d26" = 22
  constraint horizontal L8
  constraint vertical L9
  constraint horizontal L10
  constraint vertical L11
  measures "d23" horizontal distance of L1.end L8.start
  measures "d24" horizontal distance of L2.end L8.end
  measures "d25" vertical distance of L2.end L8.end
  measures "d26" distance of L8.start L10.end
extrude "Extrude5" cut sketch "Sketch7" against normal blind 12.7 contours L8 L9 L10 L11 bodies 1
sketch "Sketch22" plane through (108.6126, 1.5061, 0) normal (-0.999904, -0.013865, 0) x (0.013865, -0.999904, 0)
  line L0 (-12.6988, 0) -> (-12.6988, 12.7)
  line L1 (-12.6988, 12.7) -> (-42.2796, 12.7)
  line L2 (-42.2796, 12.7) -> (-42.2796, 0)
  line L3 (-42.2796, 0) -> (-12.6988, 0)
  line L4 (-39.1046, 12.7) -> (-17.2708, 12.7)
  line L5 (-17.2708, 12.7) -> (-17.2708, 0)
  line L6 (-17.2708, 0) -> (-39.1046, 0)
  line L7 (-39.1046, 0) -> (-39.1046, 12.7)
  dimension "d110" = 3.175
  dimension "d111" = 4.572
  constraint horizontal L4
  constraint vertical L5
  constraint horizontal L6
  constraint vertical L7
  constraint coincident L1 L4.start
  constraint coincident L3 L6.end
  measures "d110" distance of L2 L7
  measures "d111" distance of L0 L5
extrude "Extrude16" cut sketch "Sketch22" against normal blind 7.62 contours L1 L3 L4 L5 L6 L7 bodies 1
fillet "Fillet2" radius 12.7 1 edges at (108.4365, 14.2037, 6.35) on bodies 1
sketch "Sketch10" plane through (0, 0, 0) normal (0, 0, -1) x (1, 0, 0)
  line L0 (156.845, -3.2206) -> (0, 0)
  line L1 (0, 0) -> (0, -12.7)
  line L2 (0, -12.7) -> (98.6791, -14.0683)
  arc A0 (108.3731, -18.7752) -> (98.6791, -14.0683) centre (98.503, -26.7671) ccw
  line L3 (108.0704, -40.607) -> (108.0263, -43.7816)
  line L4 (108.0263, -43.7816) -> (190.0185, -44.9186)
  line L5 (190.0185, -44.9186) -> (190.4286, -15.3406)
  line L6 (156.845, -14.8749) -> (156.845, -3.2206)
  line L7 (111.2013, -18.6066) -> (188.431, -18.6066)
  line L8 (188.431, -18.6066) -> (188.431, -40.6066)
  line L9 (188.431, -40.6066) -> (115.6911, -40.6066)
  line L10 (111.2013, -18.8144) -> (111.2013, -18.6066)
  line L11 (181.1874, -40.6066) -> (181.1293, -44.7953)
  line L12 (132.205, -40.6066) -> (132.1563, -44.1163)
  line L13 (185.4208, -15.2712) -> (156.845, -14.8749)
  line L14 (115.6896, -40.7126) -> (108.0704, -40.607)
  line L15 (108.3731, -18.7752) -> (111.2013, -18.8144)
  line L16 (115.6911, -40.6066) -> (115.6896, -40.7126)
  line L17 (190.4286, -15.3406) -> (185.4208, -15.2712)
  dimension "d44" = 8.89
  dimension "d45" = 24.13
  constraint coincident L9 L11.start
  constraint coincident L4 L11.end
  constraint perpendicular L4 L11
  constraint coincident L9 L12.start
  constraint coincident L4 L12.end
  constraint perpendicular L4 L12
  measures "d44" distance of L5 L11
  measures "d45" horizontal distance of L3.end L12.end
sketch "Sketch18" plane through (0, 0, 12.7) normal (0, 0, 1) x (-1, 0, 0)
  line L0 (-190.5, -10.1919) -> (-185.4208, -15.2712)
  line L1 (-190.4286, -15.3406) -> (-190.0185, -44.9186)
  line L2 (-190.0185, -44.9186) -> (-108.0263, -43.7816)
  line L3 (-108.0263, -43.7816) -> (-108.0704, -40.607)
  arc A0 (-98.6791, -14.0683) -> (-108.3731, -18.7752) centre (-98.503, -26.7671) ccw
  line L4 (-98.6791, -14.0683) -> (0, -12.7)
  line L5 (0, -12.7) -> (0, 0)
  line L6 (0, 0) -> (-190.5, -3.9116)
  line L7 (-190.5, -3.9116) -> (-190.5, -10.1919)
  line L8 (-152.4, -3.1293) -> (-149.3556, -8.4023)
  line L9 (-149.3556, -8.4023) -> (-42.4994, -8.4023)
  line L10 (-42.4994, -8.4023) -> (-38.1, -0.7823)
  line L11 (-111.2013, -18.8144) -> (-108.3731, -18.7752)
  line L12 (-108.0704, -40.607) -> (-115.6896, -40.7126)
  line L13 (-115.6896, -40.7126) -> (-115.6911, -40.6066)
  line L14 (-115.6911, -40.6066) -> (-188.431, -40.6066)
  line L15 (-188.431, -40.6066) -> (-188.431, -18.6066)
  line L16 (-188.431, -18.6066) -> (-111.2013, -18.6066)
  line L17 (-111.2013, -18.6066) -> (-111.2013, -18.8144)
  line L18 (-185.4208, -15.2712) -> (-190.4286, -15.3406)
  dimension "d87" = 120
  dimension "d88" = 120
  dimension "d89" = 7.62
  dimension "d114" = 38.1
  dimension "d115" = 38.1
  constraint coincident L6 L8.start
  constraint coincident L6 L10.end
  constraint horizontal L9
  measures "d87" angle of L8 L9
  measures "d88" angle of L9 L10
  measures "d89" vertical distance of L9.end L10.end
  measures "d114" distance of L5 L10.end
  measures "d115" horizontal distance of L6.end L8.start
extrude "Extrude12" cut sketch "Sketch18" against normal blind 12.7 contours L6 L8 L9 L10 bodies 1
fillet "Fillet5" radius 50.8 1 edges at (149.3556, 8.4023, 6.35) on bodies 1
fillet "Fillet6" radius 50.8 1 edges at (42.4994, 8.4023, 6.35) on bodies 1